Autodesk Inventor part; units mm, degrees
(part 2 of 2)
sketch "S8_m3_-1" plane through (0, 0, 0) normal (0, 0, -1) x (0, 1, 0)
  spline S0 degree 4 poles (-120, 72.7624) (-119.8438, 72.7681) (-119.5313, 72.7795) (-119.0625, 72.7965) (-118.4376, 72.819) (-117.8126, 72.8415) (-117.1876, 72.8638) (-116.5626, 72.886) (-115.9376, 72.9082) (-115.3126, 72.9302) (-114.6877, 72.9521) (-114.0627, 72.9739) (-113.4377, 72.9956) (-112.8127, 73.0173) (-112.1877, 73.0388) (-111.5627, 73.0603) (-110.9377, 73.0817) (-110.3127, 73.103) (-109.6877, 73.1242) (-109.0627, 73.1454) (-108.4377, 73.1665) (-107.8127, 73.1875) (-107.1877, 73.2084) (-106.5627, 73.2293) (-105.9377, 73.2501) (-105.3127, 73.2709) (-104.6877, 73.2916) (-104.0627, 73.3123) (-103.4377, 73.3329) (-102.8126, 73.3535) (-102.1876, 73.374) (-101.5626, 73.3945) (-100.9376, 73.415) (-100.3126, 73.4354) (-99.6876, 73.4558) (-99.0626, 73.4761) (-98.4376, 73.4964) (-97.8126, 73.5168) (-97.1875, 73.537) (-96.5625, 73.5573) (-95.9375, 73.5776) (-95.4688, 73.5928) (-95.1563, 73.6029) (-95, 73.6079) knots 0 0 0 0 0 0.025 0.05 0.075 0.1 0.125 0.15 0.175 0.2 0.225 0.25 0.275 0.3 0.325 0.35 0.375 0.4 0.425 0.45 0.475 0.5 0.525 0.55 0.575 0.6 0.625 0.65 0.675 0.7 0.725 0.75 0.775 0.8 0.825 0.85 0.875 0.9 0.925 0.95 0.975 1 1 1 1 1
  line L0 (-95, 73.6079) -> (-95, 75.1079)
  spline S1 degree 4 poles (-95, 75.1079) (-95.1563, 75.1029) (-95.4688, 75.0928) (-95.9375, 75.0776) (-96.5625, 75.0573) (-97.1875, 75.037) (-97.8126, 75.0168) (-98.4376, 74.9964) (-99.0626, 74.9761) (-99.6876, 74.9558) (-100.3126, 74.9354) (-100.9376, 74.915) (-101.5626, 74.8945) (-102.1876, 74.874) (-102.8126, 74.8535) (-103.4377, 74.8329) (-104.0627, 74.8123) (-104.6877, 74.7916) (-105.3127, 74.7709) (-105.9377, 74.7501) (-106.5627, 74.7293) (-107.1877, 74.7084) (-107.8127, 74.6875) (-108.4377, 74.6665) (-109.0627, 74.6454) (-109.6877, 74.6242) (-110.3127, 74.603) (-110.9377, 74.5817) (-111.5627, 74.5603) (-112.1877, 74.5388) (-112.8127, 74.5173) (-113.4377, 74.4956) (-114.0627, 74.4739) (-114.6877, 74.4521) (-115.3126, 74.4302) (-115.9376, 74.4082) (-116.5626, 74.386) (-117.1876, 74.3638) (-117.8126, 74.3415) (-118.4376, 74.319) (-119.0625, 74.2965) (-119.5313, 74.2795) (-119.8438, 74.2681) (-120, 74.2624) knots 0 0 0 0 0 0.025 0.05 0.075 0.1 0.125 0.15 0.175 0.2 0.225 0.25 0.275 0.3 0.325 0.35 0.375 0.4 0.425 0.45 0.475 0.5 0.525 0.55 0.575 0.6 0.625 0.65 0.675 0.7 0.725 0.75 0.775 0.8 0.825 0.85 0.875 0.9 0.925 0.95 0.975 1 1 1 1 1
  line L1 (-120, 74.2624) -> (-120, 72.7624)
  line L2 (-191.78, 0) -> (221.78, 0) projected
  point P0 (-117.5, 72.8526)
  point P1 (-115, 72.9411)
  point P2 (-112.5, 73.0281)
  point P3 (-110, 73.1136)
  point P4 (-107.5, 73.198)
  point P5 (-105, 73.2813)
  point P6 (-102.5, 73.3638)
  point P7 (-100, 73.4456)
  point P8 (-97.5, 73.5269)
  point P9 (-97.5, 75.0269)
  point P10 (-100, 74.9456)
  point P11 (-102.5, 74.8638)
  point P12 (-105, 74.7813)
  point P13 (-107.5, 74.698)
  point P14 (-110, 74.6136)
  point P15 (-112.5, 74.5281)
  point P16 (-115, 74.4411)
  point P17 (-117.5, 74.3526)
  constraints: 4 end point, 22 other
revolve "M3_patch_shank_v8" add sketch "S8_m3_-1" angle 31.31 mid plane about axis through (0, -10, 0) along (0, 1, 0) separate body
combine bodies "Velcro_v8" operation type add bodies to combine 1 2 3 4 5 6
fillet "Corners_R3_v8" radius 3 24 edges at (-80.3653, 137.3, 57.2201) (-22.6188, 137.3, 96.0267) (-83.6582, 162.7, 59.5646) (-23.5455, 162.7, 99.9612) (70.7854, -120, 19.8369) (70.7854, -120, -19.8369) (71.5995, -95, 20.0651) (71.5995, -95, -20.0651) (-43.9252, -132.7, -50.7068) (-65.4473, -132.7, 14.7393) (-44.5067, -107.3, -51.3781) (-66.3138, -107.3, 14.9344) (-73.8025, 9.6, 8.1904) (-39.0131, 9.6, 63.1812) (-85.0742, 60.4, 9.4413) (-44.9715, 60.4, 72.8308) (-49.755, -60.4, -48.619) (-67.3025, -60.4, 17.5995) (-51.6851, -9.6, -50.505) (-69.9133, -9.6, 18.2822) (95.7742, 95, 19.5919) (95.7742, 95, -19.5919) (99.8292, 120, 20.4215) (99.8292, 120, -20.4215)
equation "\"d8\" = d7"
body "Solid2"
body "Solid3"
body "Solid4"
body "Solid5"
body "Solid6"
body "Solid7"
body "Solid8"
body "Solid9"
